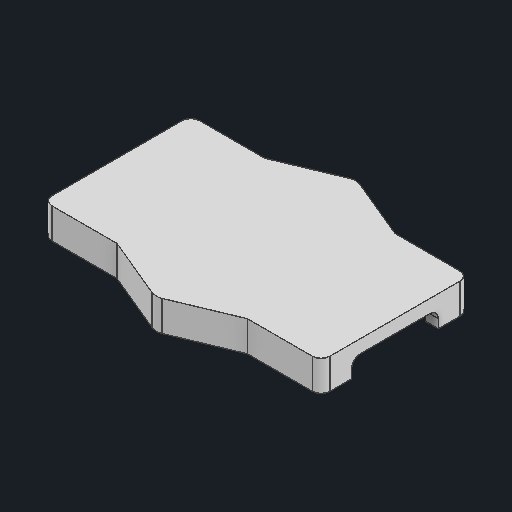
# Autodesk Inventor part: 케이스
Saved by Autodesk Inventor 2027 (Build 310192000, 192)
## iProperties
Created: 2026-09-22
Part Number: 케이스
Material: 일반
Document SubType Name: Modeling
Designer: khw
Density: 1 g/cm^3
Appearance: 기본값
Author: khw
Autodesk Inventor part; units mm, degrees
ref_plane "YZ Plane" through (0, 0, 0) normal (1, 0, 0) x (0, 1, 0)
ref_plane "XZ Plane" through (0, 0, 0) normal (0, 1, 0) x (-1, 0, 0)
ref_plane "XY Plane" through (0, 0, 0) normal (0, 0, 1) x (1, 0, 0)
sketch "스케치1" plane through (0, 0, 0) normal (0, 1, 0) x (-1, 0, 0)
  line L0 (0, 0) -> (58, 0)
  line L1 (58, 0) -> (58, -28)
  line L2 (58, -28) -> (0, -28)
  line L3 (0, -28) -> (0, 0)
  line L4 (61, -31) -> (61, 3)
  line L5 (61, 3) -> (-3, 3)
  line L6 (-3, 3) -> (-3, -31)
  line L7 (-3, -31) -> (61, -31)
  line L8 (58, -4.75) -> (61, -4.75)
  line L9 (61, -4.75) -> (61, -23.25)
  line L10 (61, -23.25) -> (58, -23.25)
  line L11 (58, -23.25) -> (58, -4.75)
  circle A0 centre (29, 6) radius 1.5
  line L12 (-3, -14) -> (58, -14) construction
  circle A1 centre (29, 6) radius 3
  line L13 (30.1538, 8.7692) -> (44, 3)
  line L14 (29, 3) -> (29, -14) construction
  line L15 (27.8462, 8.7692) -> (14, 3)
  circle A2 centre (29, -34) radius 1.5
  circle A3 centre (29, -34) radius 3
  line L16 (30.1538, -36.7692) -> (44, -31)
  line L17 (27.8462, -36.7692) -> (14, -31)
  line L18 (0, -4) -> (-3, -4)
  line L19 (-3, -4) -> (-3, -24)
  line L20 (-3, -24) -> (0, -24)
  line L21 (0, -24) -> (0, -4)
  point P0 (61, -14)
  point P1 (59.5, -23.25)
  point P2 (59.5, -4.75)
  point P3 (0, -14)
  point P4 (-1.5, -24)
  point P5 (-1.5, -4)
  point P6 (0, -24)
  dimension "d5" = 6
  dimension "d0" = 28
  dimension "d1" = 58
  dimension "d2" = 3
  dimension "d3" = 18.5
  dimension "d4" = 3
  dimension "d6" = 15
  dimension "d7" = 20
  constraints: 44 end point, 12 midpoint, 8 parallel, 8 symmetric about line, 5 horizontal, 5 perpendicular, 3 point on line, 2 centre point, 2 coincident, 1 vertical alignment, 11 other
  measures "d0" distance of L0.end L1.end
  measures "d1" distance of L1.end L2.end
  measures "d2" distance between parallel lines of L1 L4
  measures "d3" distance of point (59.5, -23.25) point (59.5, -4.75)
  measures "d4" diameter of A0
  measures "d6" distance of L14.start L13.end
  measures "d7" distance of point (-1.5, -24) point (-1.5, -4)
extrude "돌출1" add sketch "스케치1" along normal blind 3 contours L3 L18 L6 L5 L4 L8 L1 L0 | L0 L1 L2 L3 | L3 L20 L6 L18 | L8 L4 L10 L1 | L3 L2 L1 L10 L4 L7 L6 L20 | L15 A1 L5 | L5 A1 L13 | L7 A3 L17 | A1 | L16 A3 L7 | A3 | A0 | A2
extrude "돌출2" add sketch "스케치1" against normal blind 4 contours L3 L18 L6 L5 L4 L8 L1 L0 | L3 L2 L1 L10 L4 L7 L6 L20 | L15 A1 L5 | L5 A1 L13 | L7 A3 L17 | A1 | L16 A3 L7 | A3
fillet "모깎기1" radius 2 8 edges at (-61, -0.5, 3) (-61, -0.5, -31) (3, 1.5, -31) (3, -2, -31) (3, 1.5, 3) (3, -2, 3) (1.5, 0, -4) (1.5, 0, -24)
